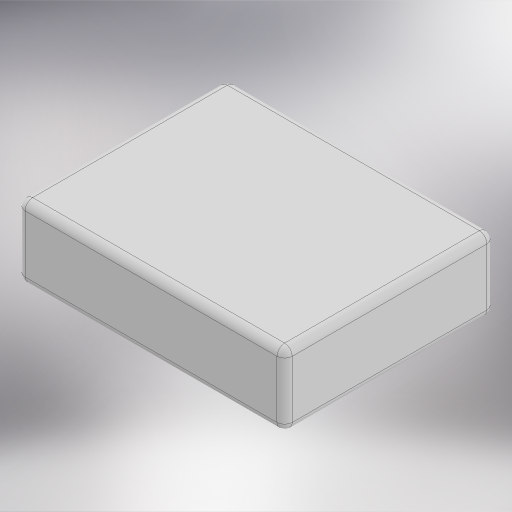
# Autodesk Inventor part: dummy_batt
Saved by Autodesk Inventor 2023.5 (Build 275446000, 446)
## iProperties
Created: 2026-10-31
Part Number: dummy_batt
Material: Generic
Document SubType Name: Modeling
Designer: WORKPLUS
Density: 1 g/cm^3
Appearance: Default
Author: WORKPLUS
Autodesk Inventor part; units mm, degrees
ref_plane "YZ Plane" through (0, 0, 0) normal (1, 0, 0) x (0, 1, 0)
ref_plane "XZ Plane" through (0, 0, 0) normal (0, 1, 0) x (-1, 0, 0)
ref_plane "XY Plane" through (0, 0, 0) normal (0, 0, 1) x (1, 0, 0)
sketch "Sketch1" plane through (0, 0, 0) normal (0, 1, 0) x (-1, 0, 0)
  line L0 (-35, -27.5) -> (35, -27.5)
  line L1 (35, -27.5) -> (35, 27.5)
  line L2 (35, 27.5) -> (-35, 27.5)
  line L3 (-35, 27.5) -> (-35, -27.5)
  line L4 (-35, -27.5) -> (35, 27.5) construction
  line L5 (35, -27.5) -> (-35, 27.5) construction
  point P0 (0, 0)
  dimension "d0" = 55
  dimension "d1" = 70
  constraints: 12 end point, 2 midpoint, 2 parallel, 1 horizontal, 1 perpendicular
  measures "d0" distance of L0.end L1.end
  measures "d1" distance of L1.end L2.end
extrude "Extrusion1" add sketch "Sketch1" along normal blind 19
fillet "Fillet1" radius 2 12 edges at (0, 19, 27.5) (35, 19, 0) (0, 19, -27.5) (-35, 19, 0) (0, 0, 27.5) (35, 0, 0) (35, 9.5, 27.5) (35, 9.5, -27.5) (0, 0, -27.5) (-35, 9.5, -27.5) (-35, 0, 0) (-35, 9.5, 27.5)
body "Solid1"
